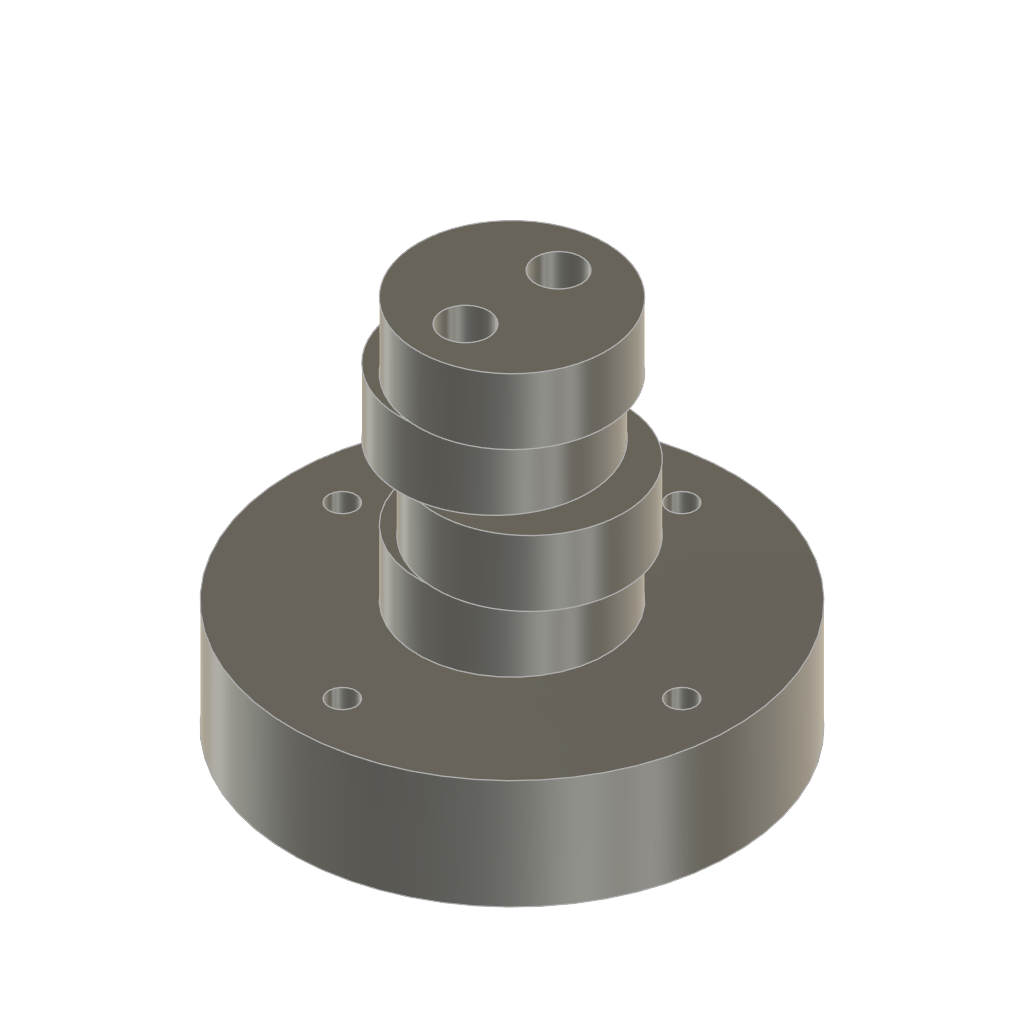
Cyclooidal_Drive (Autodesk Fusion 360 archive; units mm, degrees)
design "ec_shaft_v2"
part number: 2026-10-15-22-03-26-646
part number: 2026-10-15-22-15-17-218
part number: 2026-10-15-22-15-17-227
part number: 2026-10-15-22-15-17-230
part number: 2026-10-15-22-15-17-233
Autodesk Fusion 360 part; units mm, degrees
sketch "Sketch1" plane through (0, 0, 0) normal (0, 0, 1) x (1, 0, 0)
  circle A0 centre (0, 0) radius 8.575
  dimension "d1" = 17.15
  constraint coincident A0.centre origin
  measures "d1" diameter of A0
extrude "Extrude1" add sketch "Sketch1" along normal blind 6 makes body 1
sketch "Sketch2" plane through (0, 0, 6) normal (0, 0, 1) x (-1, 0, 0)
  circle A0 centre (0, 0) radius 8.575
  circle A1 centre (-1.6, 0) radius 8.575
  dimension "d4" = 17.15
  dimension "d5" = 1.6
  measures "d4" diameter of A1
  measures "d5" distance of A0.centre A1.centre
extrude "Extrude2" add sketch "Sketch2" along normal blind 6 separate body contours A0 A1 | A0 A1 picked at (1.7605, -0.4207) picked at (-9.0697, -0.6274) makes body 2
sketch "Sketch3" plane through (0, 0, 12) normal (0, 0, 1) x (-1, 0, 0)
  circle A0 centre (-1.6, 0) radius 8.575
  circle A1 centre (1.6, 0) radius 8.575
  dimension "d8" = 17.15
  dimension "d9" = 1.6
  measures "d8" diameter of A1
  measures "d9" distance of origin A1.centre
extrude "Extrude3" add sketch "Sketch3" along normal blind 6 separate body contours A0 A1 | A0 A1 picked at (-2.3099, 0) picked at (8.9285, 1.6372) makes body 3
extrude "Extrude4" add sketch "Sketch1" along normal blind 6 from surface at 18 separate body makes body 4
sketch "Sketch4" plane through (0, 0, 24) normal (0, 0, 1) x (-1, 0, 0)
  circle A0 centre (0, 0) radius 8.575
  point P0 (0, -4.25)
  point P1 (0, 4.25)
  dimension "d15" = 8.5
  dimension "d16" = 4.25
  measures "d15" distance of P0 P1
  measures "d16" distance of P1 A0.centre
hole "Hole1" at (0, 4.25, 24) at (0, -4.25, 24) direction (0, 0, -1) diameter 4.2 depth 24 tip angle 180 bodies 2 4 3 1
sketch "Sketch5" plane through (0, 0, 0) normal (0, 0, -1) x (1, 0, 0)
  circle A0 centre (0, -4.25) radius 2.1
  circle A1 centre (0, 4.25) radius 2.1
  circle A2 centre (0, 0) radius 8.575
  circle A3 centre (0, 0) radius 20.15
  dimension "d20" = 40.3
  constraint coincident A2.centre A3.centre
  measures "d20" diameter of A3
extrude "Extrude5" add sketch "Sketch5" along normal blind 10 contours A0 | A1 | A2 | A3 bodies 1
copy_body "Body->Comp1" bodies 1 removing the originals makes body 5 in component "Component"
copy_body "Body->Comp2" bodies 3 removing the originals makes body 6 in component "Component'"
copy_body "Body->Comp3" bodies 4 removing the originals makes body 7 in component "Component''"
copy_body "Body->Comp4" bodies 2 removing the originals makes body 8 in component "Component'''"
sketch "Sketch6" plane through (0, 0, -10) normal (0, 0, -1) x (1, 0, 0)
  circle A0 centre (0, 0) radius 20.15
  circle A1 centre (15.5, 0) radius 1.25
  line L0 (1.75, 0) -> (22.5, 0)
  circle A2 centre (0, 15.5) radius 1.25
  circle A3 centre (-15.5, 0) radius 1.25
  circle A4 centre (0, -15.5) radius 1.25
  circle A5 centre (0, 0) radius 1.8
  dimension "d23" = 2.5
  dimension "d24" = 15.5
  dimension "d26" = 360
  dimension "d27" = 3.6
  constraint coincident A1.centre L0
  constraint coincident A0.centre A5.centre
  measures "d23" diameter of A1
  measures "d24" distance of A0.centre A1.centre
  measures "d27" diameter of A5
extrude "Extrude1'" cut sketch "Sketch6" against normal up to surface (10 mm away) contours A1 L0 | A1 L0 | A2 | A3 | A4 | A5 bodies 5 in component "Component"
component "Component" placed x (1, 0, 0) y (0, 1, 0) z (0, 0, 1) at (0, 0, 0)
component "Component'" placed x (1, 0, 0) y (0, 1, 0) z (0, 0, 1) at (0, 0, 0)
component "Component''" placed x (1, 0, 0) y (0, 1, 0) z (0, 0, 1) at (0, 0, 0)
component "Component'''" placed x (1, 0, 0) y (0, 1, 0) z (0, 0, 1) at (0, 0, 0)
equation "d15 = ( 17 / 2 ) * 1 mm"
equation "d16 = ( 17 / 4 ) * 1 mm"

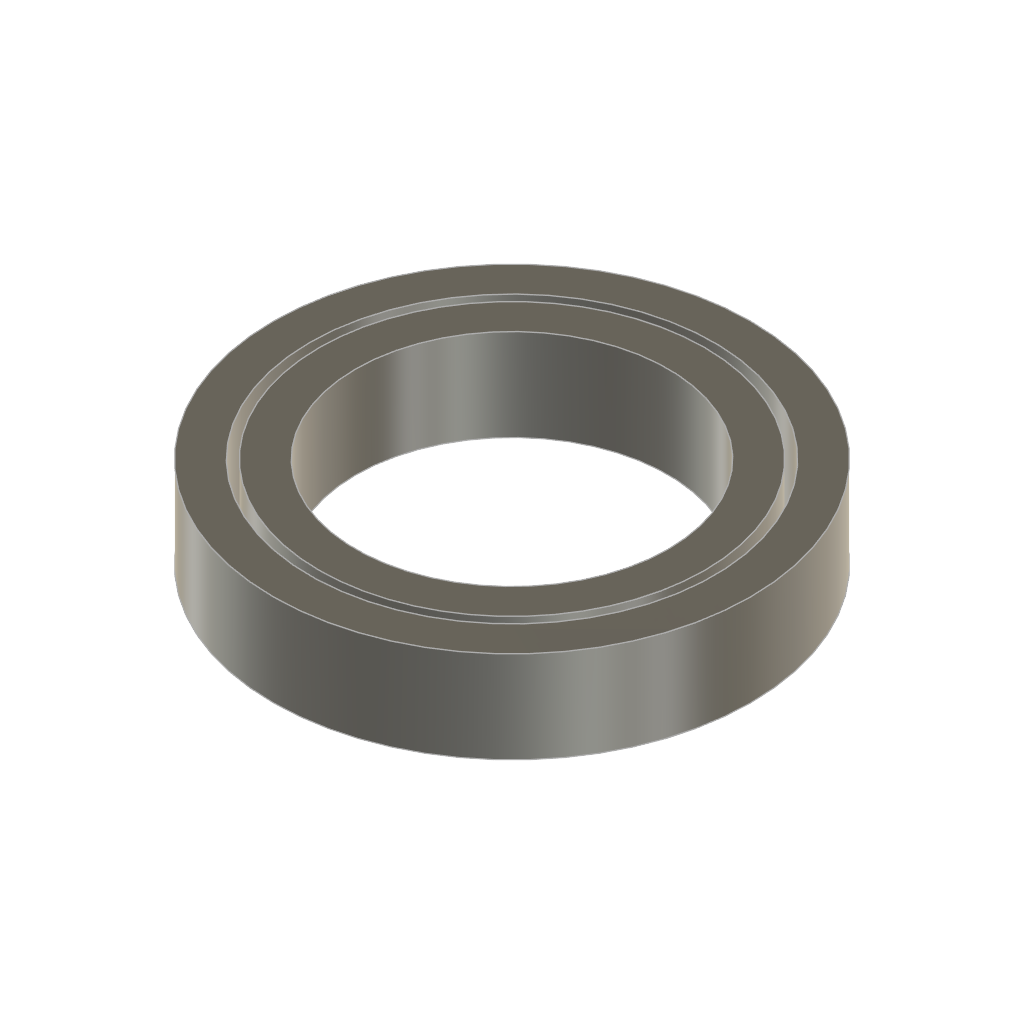
design "thin_section_bearing_17x26x5"
part number: 2026-10-01-12-30-01-607
part number: 2026-10-01-12-55-07-303
part number: 2026-10-01-12-55-35-532
Autodesk Fusion 360 part; units mm, degrees
sketch "Sketch1" plane through (0, 0, 0) normal (0, 0, 1) x (1, 0, 0)
  circle A0 centre (0, 0) radius 8.5
  circle A1 centre (0, 0) radius 13
  circle A2 centre (0, 0) radius 11
  circle A3 centre (0, 0) radius 10.5
  dimension "d1" = 17
  dimension "d2" = 26
  dimension "d3" = -2
  dimension "d4" = 2
  constraint coincident A0.centre A1.centre
  constraint concentric A0 A1
  measures "d1" diameter of A0
  measures "d2" diameter of A1
extrude "Extrude1" add sketch "Sketch1" along normal blind 5 contours A1 makes body 1 in component "Component"
extrude "Extrude1'" add sketch "Sketch1" along normal blind 5 separate body contours A3 makes body 2 in component "Component'"
component "Component" placed x (1, 0, 0) y (0, 1, 0) z (0, 0, 1) at (0, 0, 0)
component "Component'" placed x (1, 0, 0) y (0, 1, 0) z (0, 0, 1) at (0, 0, 0)
